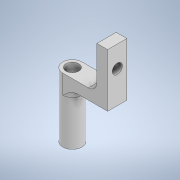
# Autodesk Inventor part: suport_reed_canal
Saved by Autodesk Inventor 2022.6 (Build 266554000, 554)
## iProperties
Created: 2025-11-25
Part Number: suport_reed_canal
Material: Generic
Document SubType Name: Modeling
Designer: Dragos Macovei
Density: 1 g/cm^3
Appearance: Default
Author: Dragos Macovei
Autodesk Inventor part; units mm, degrees
ref_plane "YZ Plane" through (0, 0, 0) normal (1, 0, 0) x (0, 1, 0)
ref_plane "XZ Plane" through (0, 0, 0) normal (0, 1, 0) x (-1, 0, 0)
ref_plane "XY Plane" through (0, 0, 0) normal (0, 0, 1) x (1, 0, 0)
sketch "Sketch1" plane through (0, 0, 0) normal (0, 1, 0) x (-1, 0, 0)
  circle A0 centre (0, 0) radius 3
  circle A1 centre (0, 0) radius 4.5
  dimension "d0" = 6
  dimension "d1" = 9
  constraints: 2 centre point, 2 coincident
  measures "d0" diameter of A0
  measures "d1" diameter of A1
extrude "Extrusion1" add sketch "Sketch1" along normal blind 30
sketch "Sketch2" plane through (0, 0, 0) normal (1, 0, 0) x (0, 1, 0)
  line L0 (30, -4.5) -> (30, 4.5) projected
  line L1 (0, -4.5) -> (0, 4.5) projected
  line L2 (0, -4.5) -> (30, -4.5) projected
  line L3 (30, 4.5) -> (25, 4.5)
  line L4 (25, 4.5) -> (25, -4.5)
  line L5 (25, -4.5) -> (30, -4.5)
  line L6 (30, -4.5) -> (30, 4.5)
  point P0 (0, 0)
  dimension "d4" = 5
  constraints: 8 end point, 2 parallel, 1 horizontal, 1 perpendicular, 1 point on line
  measures "d4" distance of L5.end L4.end
extrude "Extrusion2" add sketch "Sketch2" along normal blind 21
sketch "Sketch3" plane through (0, 30, 0) normal (0, 1, 0) x (1, 0, 0)
  line L0 (21, 4.5) -> (21, -4.5) projected
  line L1 (0, 4.5) -> (21, 4.5) projected
  line L2 (21, -4.5) -> (16, -4.5)
  line L3 (16, -4.5) -> (16, 4.5)
  line L4 (16, 4.5) -> (21, 4.5)
  line L5 (21, 4.5) -> (21, -4.5)
  point P0 (0, 0)
  dimension "d7" = 5
  constraints: 8 end point, 2 parallel, 1 horizontal, 1 perpendicular, 1 point on line
  measures "d7" distance of L3.end L4.end
extrude "Extrusion3" add sketch "Sketch3" along normal blind 20
sketch "Sketch4" plane through (16, 30, -4.5) normal (-1, 0, 0) x (0, 0, 1)
  circle A0 centre (4.5, 10) radius 2.332
  line L0 (0, 20) -> (9, 20) projected
  point P0 (4.5, -30)
  point P1 (4.5, 20)
  dimension "d10" = 10
  constraints: 1 centre point, 1 midpoint
  measures "d10" distance of point (4.5, 20) A0.centre
extrude "Extrusion4" cut sketch "Sketch4" against normal blind 20
sketch "Sketch5" plane through (0, 0, 0) normal (0, -1, 0) x (1, 0, 0)
  circle A0 centre (0, 0) radius 3 projected
  circle A1 centre (0, 0) radius 4.5 projected
extrude "Extrusion5" cut sketch "Sketch5" against normal through all contours A0
fillet "Fillet1" radius 4 2 edges at (4.5, 25, 0) (16, 30, 0)
body "Solid1"
